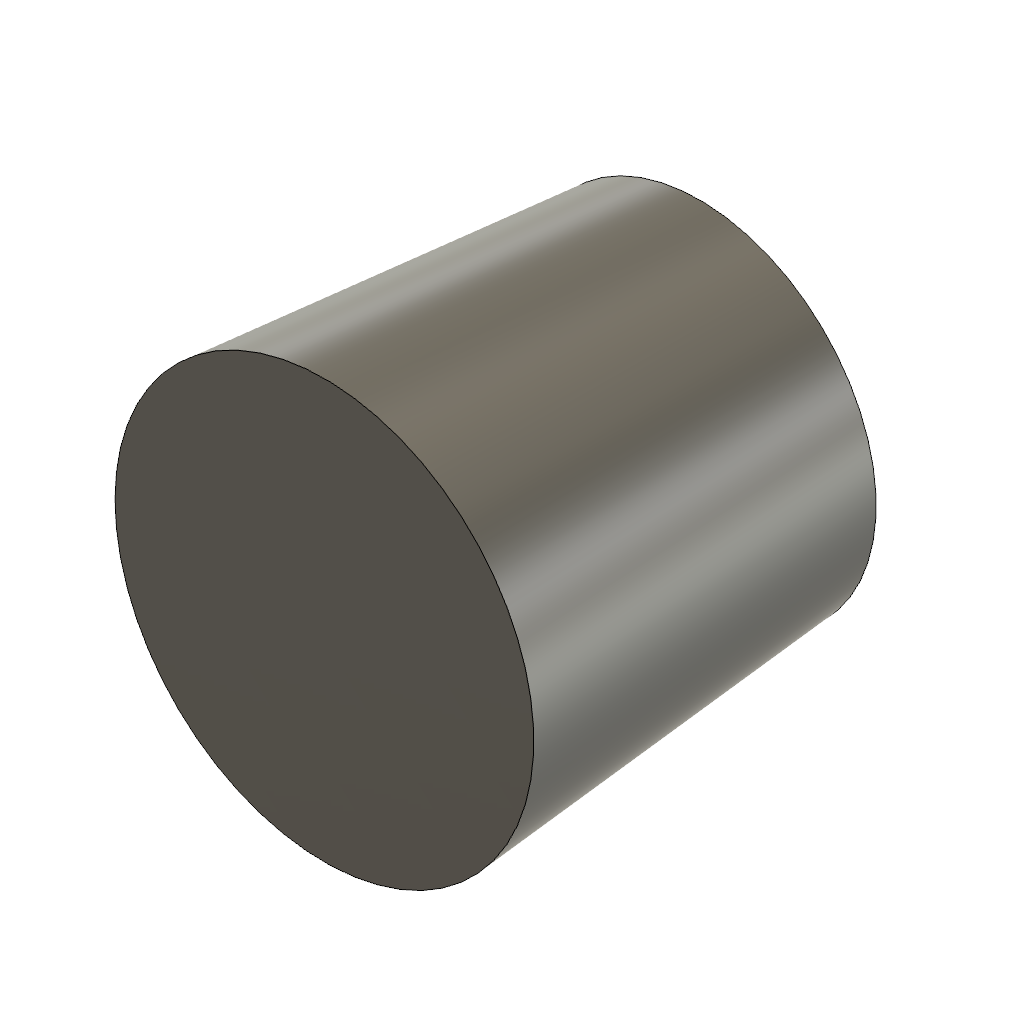
drafted_extrusion (Autodesk Fusion 360 design; units mm, degrees)
part number: 2026-10-20-16-47-00-166
Autodesk Fusion 360 part; units mm, degrees
sketch "IndependentProfile0" plane through (0, 0, 0) normal (0, 0, 1) x (1, 0, 0)
  circle A0 centre (0, 0) radius 10
extrude "BlindProbe_0" add sketch "IndependentProfile0" along normal blind 21.25 draft 5
